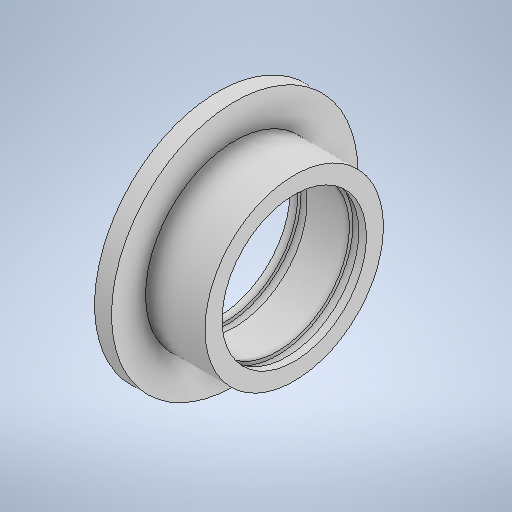
# Autodesk Inventor part: Tuleja_lożyskowa
Saved by Autodesk Inventor 2025.2 (Build 292293000, 293)
## iProperties
Created: 2025-04-06
Part Number: Tuleja_lożyskowa
Material: Generic
Document SubType Name: Modeling
Designer: makst
Density: 1 g/cm^3
Appearance: Default
Author: makst
Autodesk Inventor part; units mm, degrees
ref_plane "YZ Plane" through (0, 0, 0) normal (1, 0, 0) x (0, 1, 0)
ref_plane "XZ Plane" through (0, 0, 0) normal (0, 1, 0) x (-1, 0, 0)
ref_plane "XY Plane" through (0, 0, 0) normal (0, 0, 1) x (1, 0, 0)
sketch "Sketch1" plane through (0, 0, 0) normal (0, 1, 0) x (-1, 0, 0)
  line L0 (9, 0) -> (9, -6)
  line L1 (9, -6) -> (7, -6)
  line L2 (7, -6) -> (7, -2)
  line L3 (7, -2) -> (0, -2)
  line L4 (0, -2) -> (0, 0)
  line L5 (8, 8.5) -> (-1, 8.5)
  line L6 (9, 0) -> (8.1, 0)
  line L7 (8.1, 0) -> (8.1, -0.4)
  line L8 (8.1, -0.4) -> (7, -0.4)
  line L9 (7, -0.4) -> (7, 0)
  line L10 (9, 0) -> (8.1, 0)
  line L11 (0, 0) -> (0.9, 0)
  line L12 (0.9, 0) -> (0.9, -0.4)
  line L13 (0.9, -0.4) -> (2, -0.4)
  line L14 (2, -0.4) -> (2, 0)
  line L15 (2, 0) -> (7, 0)
  point P0 (0.9, -0.2)
  dimension "d2" = 6
  dimension "d3" = 2
  dimension "d4" = 4
  dimension "d13" = 0.9
  dimension "d14" = 0.4
  dimension "d15" = 1.1
  dimension "d17" = 0.4
  dimension "d18" = 1.1
  dimension "d20" = 17
  dimension "d21" = 0.9
  dimension "d22" = 9
  constraints: 32 end point, 8 perpendicular, 3 horizontal, 1 collinear, 1 midpoint, 1 point on line
  measures "d2" distance of L0.start L0.end
  measures "d3" distance of L0.end L1.end
  measures "d4" distance of L1.end L2.end
  measures "d13" distance of L0.start L6.end
  measures "d14" distance of L6.end L7.end
  measures "d15" distance of L7.end L8.end
  measures "d17" distance of L11.end L12.end
  measures "d18" distance of L12.end L13.end
  measures "d20" diameter of L15 L5
  measures "d21" distance from line of point (0.9, -0.2) L4
  measures "d22" distance between parallel lines of L0 L4
revolve "Revolution1" add sketch "Sketch1" angle 360 about axis through (-8, 0, 8.5) along (1, 0, 0)
body "Solid1"
